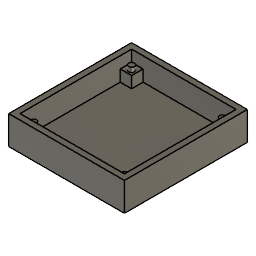
PCB Housing (Autodesk Fusion 360 design; units mm, degrees)
Autodesk Fusion 360 part; units mm, degrees
sketch "Sketch1" plane through (0, 0, 0) normal (0, 0, 1) x (1, 0, 0)
  line L0 (0, 0) -> (58, 0)
  line L1 (58, 0) -> (58, 62)
  line L2 (58, 62) -> (0, 62)
  line L3 (0, 62) -> (0, 0)
  dimension "d1" = 62
  dimension "d2" = 58
  constraint horizontal L0
  constraint vertical L1
  constraint horizontal L2
  constraint vertical L3
  constraint coincident L0.start L3.end
  measures "d1" distance of L0.start L2.end
  measures "d2" distance of L0.start L0.end
extrude "Extrude1" add sketch "Sketch1" along normal blind 3.175 makes body 1
sketch "Sketch3" plane through (0, 0, 3.175) normal (0, 0, 1) x (-1, 0, 0)
  line L0 (0, -62) -> (0, 0)
  line L1 (0, 0) -> (-58, 0)
  line L2 (-58, 0) -> (-58, -62)
  line L3 (-58, -62) -> (0, -62)
  line L4 (3.175, -65.175) -> (-61.175, -65.175)
  line L5 (-61.175, -65.175) -> (-61.175, 3.175)
  line L6 (-61.175, 3.175) -> (3.175, 3.175)
  line L7 (3.175, 3.175) -> (3.175, -65.175)
  dimension "d5" = 3.175
  dimension "d6" = 3.175
  dimension "d7" = 3.175
  dimension "d8" = 3.175
  constraint horizontal L4
  constraint vertical L5
  constraint horizontal L6
  constraint vertical L7
  measures "d5" distance of L0 L7
  measures "d6" distance of L1 L6
  measures "d7" distance of L3 L4
  measures "d8" distance of L2 L5
extrude "Extrude2" add sketch "Sketch3" along normal blind 12.7 and the other way blind 3.175 separate body makes body 2
sketch "Sketch4" plane through (0, 0, 3.175) normal (0, 0, 1) x (-1, 0, 0)
  line L0 (0, -62) -> (0, 0)
  line L1 (0, 0) -> (-58, 0)
  line L2 (-58, 0) -> (-58, -62)
  line L3 (-58, -62) -> (0, -62)
  circle A0 centre (-3.75, -58.25) radius 1.65
  circle A1 centre (-54.25, -58.25) radius 1.65
  circle A2 centre (-3.75, -3.75) radius 1.65
  circle A3 centre (-54.25, -3.75) radius 1.65
  line L4 (0, 0) -> (-6.35, 0)
  line L5 (-6.35, 0) -> (-6.35, -6.35)
  line L6 (-6.35, -6.35) -> (0, -6.35)
  line L7 (0, -6.35) -> (0, 0)
  line L8 (0, -62) -> (-6.35, -62)
  line L9 (-6.35, -62) -> (-6.35, -55.65)
  line L10 (-6.35, -55.65) -> (0, -55.65)
  line L11 (0, -55.65) -> (0, -62)
  line L12 (-58, -62) -> (-51.65, -62)
  line L13 (-51.65, -62) -> (-51.65, -55.65)
  line L14 (-51.65, -55.65) -> (-58, -55.65)
  line L15 (-58, -55.65) -> (-58, -62)
  line L16 (-58, 0) -> (-51.65, 0)
  line L17 (-51.65, 0) -> (-51.65, -6.35)
  line L18 (-51.65, -6.35) -> (-58, -6.35)
  line L19 (-58, -6.35) -> (-58, 0)
  dimension "d13" = 50.5
  dimension "d14" = 50.5
  dimension "d15" = 54.5
  dimension "d16" = 54.5
  dimension "d17" = 3.3
  dimension "d19" = 3.75
  dimension "d20" = 3.75
  dimension "d21" = 6.35
  dimension "d22" = 6.35
  dimension "d23" = 6.35
  dimension "d24" = 6.35
  dimension "d25" = 6.35
  dimension "d26" = 6.35
  dimension "d27" = 6.35
  dimension "d28" = 6.35
  constraint horizontal A0.centre A1.centre
  constraint horizontal A2.centre A3.centre
  constraint vertical A0.centre A2.centre
  constraint equal A0 A1
  constraint equal A1 A3
  constraint equal A2 A3
  constraint horizontal L4
  constraint vertical L5
  constraint horizontal L6
  constraint vertical L7
  constraint coincident L0.end L1.start
  constraint horizontal L8
  constraint vertical L9
  constraint horizontal L10
  constraint vertical L11
  constraint coincident L0.start L3.end
  constraint horizontal L12
  constraint vertical L13
  constraint horizontal L14
  constraint vertical L15
  constraint coincident L2.end L3.start
  constraint horizontal L16
  constraint vertical L17
  constraint horizontal L18
  constraint vertical L19
  constraint coincident L1.end L2.start
  measures "d13" distance of A0.centre A1.centre
  measures "d14" distance of A2.centre A3.centre
  measures "d15" distance of A0.centre A2.centre
  measures "d16" distance of A1.centre A3.centre
  measures "d17" diameter of A0
  measures "d19" distance of L1 A2.centre
  measures "d20" distance of L2 A1.centre
  measures "d21" distance of L5.end L6.end
  measures "d22" distance of L4 L6
  measures "d23" distance of L8.end L9.end
  measures "d24" distance of L9 L11
  measures "d25" distance of L13.end L14.end
  measures "d26" distance of L12 L14
  measures "d27" distance of L16 L18
  measures "d28" distance of L17 L19
extrude "Extrude3" add sketch "Sketch4" along normal blind 6.35 contours L0 L3 L8 L9 L10 L11 | L0 L1 L4 L5 L6 L7 | L2 L3 L12 L13 L14 L15 | L1 L2 L16 L17 L18 L19 | A0 | A1 | A2 | A3 bodies 1 2
extrude "Extrude4" add sketch "Sketch4" along normal blind 8.89 contours A0 | A1 | A2 | A3 bodies 1
